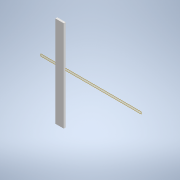
# Autodesk Inventor part: ascuns_teava_2
Saved by Autodesk Inventor 2022.6 (Build 266554000, 554)
## iProperties
Created: 2026-11-09
Part Number: ascuns_teava_2
Material: Generic
Document SubType Name: Modeling
Designer: Dragos Macovei
Density: 1 g/cm^3
Appearance: Default
Author: Dragos Macovei
Autodesk Inventor part; units mm, degrees
ref_plane "YZ Plane" through (0, 0, 0) normal (1, 0, 0) x (0, 1, 0)
ref_plane "XZ Plane" through (0, 0, 0) normal (0, 1, 0) x (-1, 0, 0)
ref_plane "XY Plane" through (0, 0, 0) normal (0, 0, 1) x (1, 0, 0)
ref_plane "Work Plane1" through (-1549.6884, -2265.8587, 30.0972) normal (0, 0, 1) x (-1, 0, 0)
sketch "Sketch1" plane through (-1549.6884, -2265.8587, 30.0972) normal (0, 0, 1) x (-1, 0, 0)
  line L0 (55.6258, 394.1358) -> (191.6258, 394.1358)
  line L1 (191.6258, 394.1358) -> (191.6258, -465.8642)
  line L2 (191.6258, -465.8642) -> (55.6258, -465.8642)
  line L3 (55.6258, -465.8642) -> (55.6258, 394.1358)
  point P0 (-1549.6884, -2265.8587)
  dimension "d0" = 136
  dimension "d1" = 860
  constraints: 8 end point, 2 parallel, 1 horizontal, 1 perpendicular
  measures "d0" distance of L1.end L2.end
  measures "d1" distance of L0.end L1.end
extrude "Extrusion1" add sketch "Sketch1" along normal blind 18
body "Solid1"
